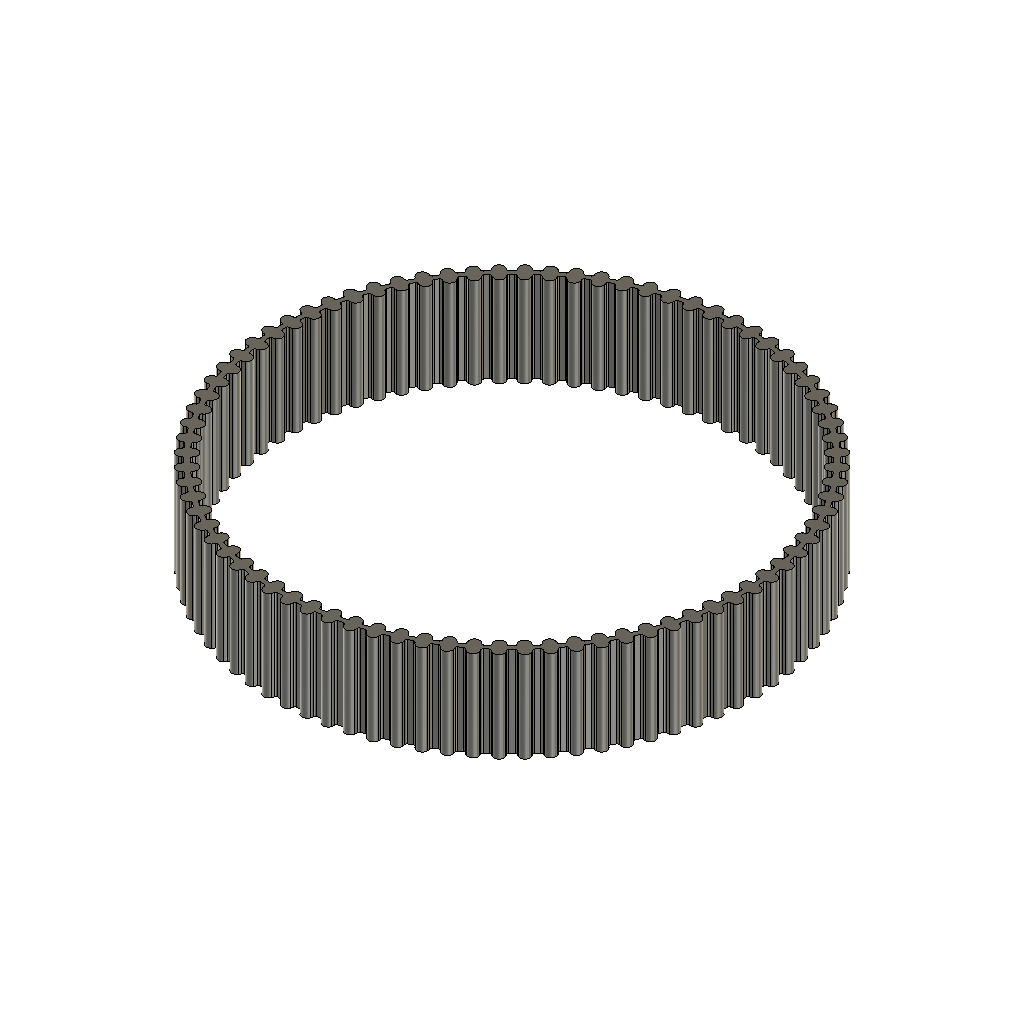
D-GT2-3M Belt Print (Autodesk Fusion 360 design; units mm, degrees)
Autodesk Fusion 360 part; units mm, degrees
sketch "Teeth" plane through (0, 0, 0) normal (0, 0, 1) x (1, 0, 0)
  circle A0 centre (0, 0) radius 38.1972
  arc A1 (0.6862, 37.1764) -> (1.4399, 36.6479) centre (1.4733, 37.4973) ccw
  line L0 (0, 0) -> (0, 7.1835) construction
  line L1 (0, 0) -> (1.4733, 37.4973) construction
  line L2 (0, 37.8162) -> (0, 38.1972)
  arc A2 (1.4996, 38.1678) -> (0, 38.1972) centre (0, 0) ccw
  arc A3 (0.3356, 37.8147) -> (0, 37.8162) centre (0, 0) ccw
  arc A4 (0.5821, 37.5909) -> (0.3356, 37.8147) centre (0.3334, 37.5647) ccw
  arc A5 (0.5821, 37.5909) -> (0.6862, 37.1764) centre (2.0937, 37.7503) ccw
  line L3 (1.4996, 38.1678) -> (2.1091, 38.1438) construction
  line L4 (2.0937, 37.7503) -> (2.1091, 38.1438) construction
  arc A6 (1.4399, 36.6479) -> (2.2328, 37.1156) centre (1.4733, 37.4973) ccw
  arc A7 (2.2328, 37.1156) -> (2.3691, 37.5207) centre (0.8746, 37.7982) ccw
  arc A8 (2.6323, 37.7245) -> (2.3691, 37.5207) centre (2.6149, 37.4751) ccw
  arc A9 (2.967, 37.6996) -> (2.6323, 37.7245) centre (0, 0) ccw
  line L5 (2.967, 37.6996) -> (2.9969, 38.0795)
  arc A10 (2.9969, 38.0795) -> (1.4996, 38.1678) centre (0, 0) ccw
  circle A11 centre (0, 0) radius 37.8162
  line L6 (0, 38.1972) -> (0, 38.5782)
  arc A12 (0.3759, 38.5764) -> (0.625, 38.7856) centre (0.3784, 38.8264) ccw
  arc A13 (0.7665, 39.2199) -> (0.625, 38.7856) centre (2.1246, 38.5374) ccw
  arc A14 (2.313, 39.1592) -> (0.7665, 39.2199) centre (1.526, 38.8383) ccw
  arc A15 (2.42, 38.715) -> (2.313, 39.1592) centre (0.9055, 38.5853) ccw
  arc A16 (2.42, 38.715) -> (2.6519, 38.487) centre (2.6691, 38.7364) ccw
  line L7 (1.4733, 37.4973) -> (1.526, 38.8383) construction
  line L8 (2.1091, 38.1438) -> (2.1246, 38.5374) construction
  arc A17 (0.3759, 38.5764) -> (0, 38.5782) centre (0, 0) ccw
  line L9 (2.9969, 38.0795) -> (3.0268, 38.4593)
  arc A18 (3.0268, 38.4593) -> (2.6519, 38.487) centre (0, 0) ccw
  point P0 (0.9055, 38.5853)
  dimension "d50" = 76.3944
  dimension "d59" = 2.25
  dimension "d67" = 0.381
  dimension "d68" = 0.25
  dimension "d69" = 1.521
  dimension "d71" = 0.61
  dimension "d72" = 0.85
  dimension "d73" = 1.52
  constraint coincident A0.centre L0.start
  constraint coincident A0 L2.end
  constraint parallel L0 L2
  constraint coincident A0 A2.start
  constraint collinear A1.centre A0.centre A2.start
  constraint coincident A1.centre L1.end
  constraint coincident L1 A1.end
  constraint vertical L0
  constraint coincident L0 L2.start
  constraint tangent A3 A4
  constraint tangent A4 A5
  constraint tangent A1 A5
  constraint tangent A0 L3
  constraint coincident A5.centre L4.start
  constraint coincident L3 L4.end
  constraint perpendicular L3 L4
  constraint coincident L3.end L4.end
  constraint symmetric A1 L1 A6
  constraint symmetric L1 L2.end L5.end
  constraint symmetric L1 A2.start L3.start
  constraint symmetric L1 A2 A10
  constraint symmetric L1 A1.end A6.start
  constraint symmetric L1 L2.start A9.start
  constraint symmetric L1 A3.start A8.start
  constraint symmetric L1 A3 A9
  constraint symmetric L1 A4.start A7.end
  constraint symmetric L1 A4 A8
  constraint symmetric L1 A1.start A6.end
  constraint symmetric L1 A5 A7
  constraint concentric A10 A11
  constraint coincident L2.start A11
  constraint perpendicular A2 L6
  constraint equal L2 L6
  constraint tangent A12 A13
  constraint tangent A13 A14
  constraint tangent A14 A15
  constraint tangent A15 A16
  constraint equal A4 A12
  constraint equal A12 A16
  constraint equal A7 A15
  constraint equal A13 A15
  constraint equal A6 A14
  constraint coincident A14.centre L7.end
  constraint perpendicular A2 L7
  constraint midpoint A2.start L7
  constraint perpendicular L3 L8
  constraint equal L4 L8
  constraint coincident A13.centre L8.end
  constraint symmetric A13.centre L7 P0
  constraint coincident P0 A15.centre
  constraint tangent A12 A17
  constraint perpendicular A0 L9
  constraint equal L6 L9
  constraint concentric A11 A17
  constraint tangent A16 A18
  constraint coincident L9.end A18.start
  measures "d50" diameter of A0
  measures "d59" angle of L0 L1
  measures "d67" distance of L2.end L2.start
  measures "d68" radius of A4
  measures "d69" distance of A2.start A1.end
  measures "d71" distance of A2.start L3.end
  measures "d72" radius of A1
  measures "d73" radius of A5
extrude "Extrude1" add sketch "Teeth" along normal mid plane 15 contours A0 L2 L5 A11 | A0 L2 A2 A3 A9 L5 A10 A11
extrude "Extrude3" add sketch "Teeth" along normal through all of body 1 and the other way through all of body 1 contours A0 L2 A2 A3 A9 L5 A10 A11 | A0 A2 A10 L6 A12 A13 A14 A15 A16 A17 L9 A18 | A1 A4 A5 A6 A7 A8 A11
pattern_circular "C-Pattern1" count 80 over 360 about axis through (0, 0, 0) along (0, 0, 1) of "Extrude3"
equation "p = 3 mm"
equation "n = 80" comment "Number of Teeth"
equation "PD = n * p / 3.14159"
equation "d25 = width"
equation "d50 = PD"
equation "d52 = n"
equation "d59 = ( 180 / n ) * 1 deg"
equation "width = 15 mm"
